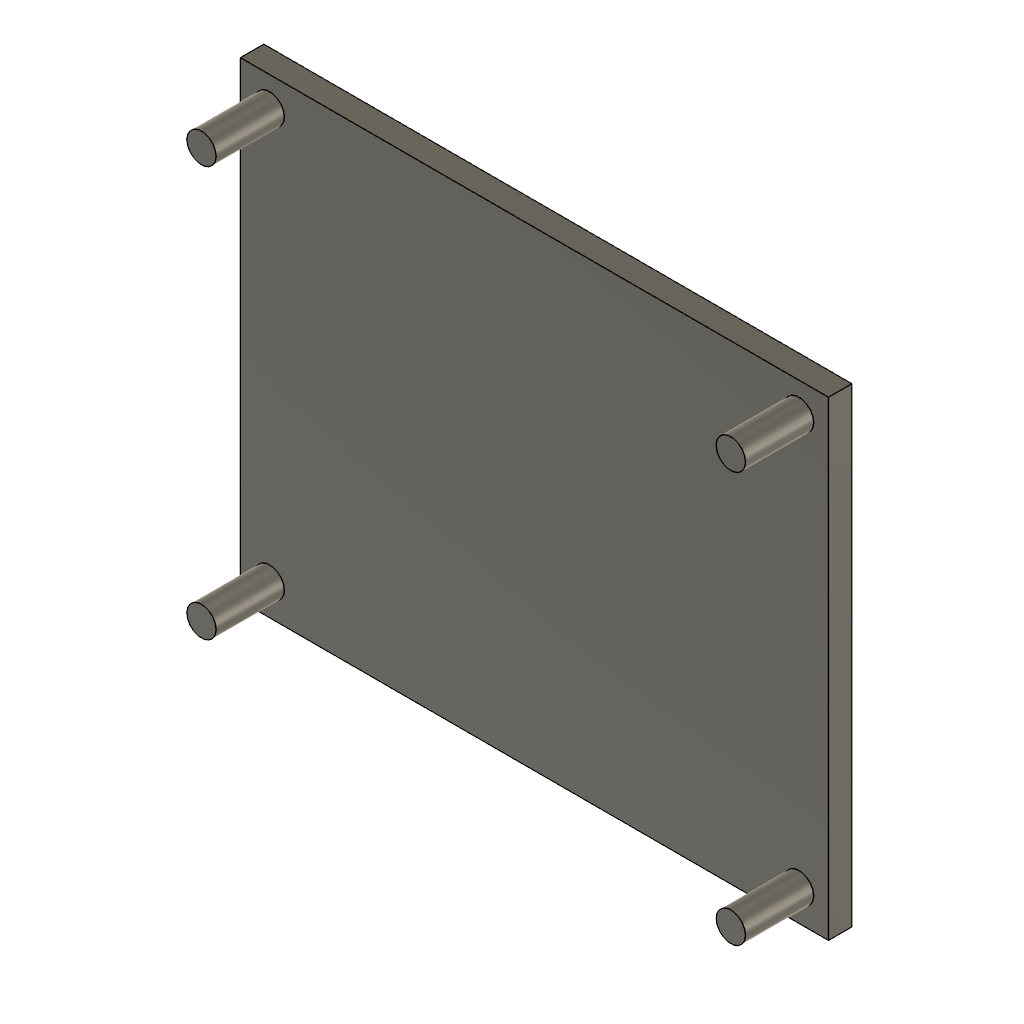
Gearbox_Housing_Lid (Autodesk Fusion 360 design; units mm, degrees)
part number: 2026-10-29-00-37-13-174
Autodesk Fusion 360 part; units mm, degrees
sketch "Sketch1" plane through (0, 0, 0) normal (0, 1, 0) x (1, 0, 0)
  line L0 (-11.2406, 0) -> (52.2594, 0)
  line L1 (52.2594, 0) -> (52.2594, -50.8)
  line L2 (52.2594, -50.8) -> (-11.2406, -50.8)
  line L3 (-11.2406, -50.8) -> (-11.2406, 0)
  dimension "d1" = 63.5
  dimension "d2" = 50.8
  constraint horizontal L0
  constraint vertical L1
  constraint horizontal L2
  constraint vertical L3
  measures "d1" distance of L0.start L0.end
  measures "d2" distance of L0.start L2.end
extrude "Extrude1" add sketch "Sketch1" along normal blind 2.54
sketch "Sketch2" plane through (0, 0, 0) normal (0, -1, 0) x (1, 0, 0)
  line L0 (52.2594, 50.8) -> (-11.2406, 50.8)
  line L1 (-11.2406, 50.8) -> (-11.2406, 0)
  line L2 (-11.2406, 0) -> (52.2594, 0)
  line L3 (52.2594, 0) -> (52.2594, 50.8)
  circle A0 centre (-8.0656, 47.625) radius 1.5875
  dimension "d5" = 3.175
  dimension "d6" = 3.175
  dimension "d7" = 3.175
  measures "d5" diameter of A0
  measures "d6" distance of L1 A0.centre
  measures "d7" distance of L0 A0.centre
extrude "Extrude2" add sketch "Sketch2" along normal blind 7.366 contours A0
pattern_linear "R-Pattern1" count 2 spacing 44.2468 along (0, 0, -1) count 2 spacing 57.15 along (1, 0, 0) of "Extrude2"
